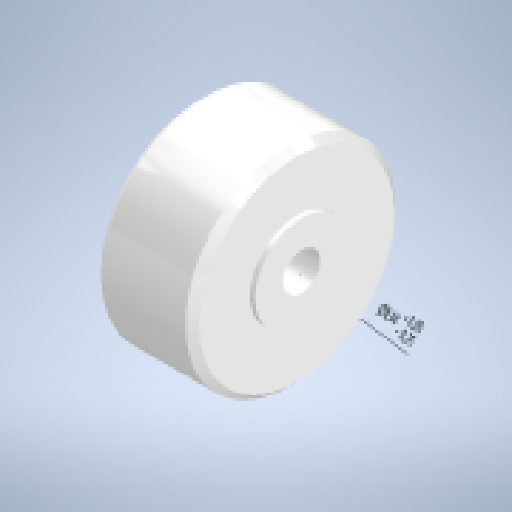
# Autodesk Inventor part: Wiel
Saved by Autodesk Inventor 2023.2 (Build 272271000, 271)
## iProperties
Created: 2023-06-25
Part Number: Wiel
Material: PAEK Plastic
Document SubType Name: Modeling
Designer: Jeroen
Density: 1.32 g/cm^3
Appearance: Smooth - White
Author: Jeroen
Autodesk Inventor part; units mm, degrees
ref_plane "YZ Plane" through (0, 0, 0) normal (1, 0, 0) x (0, 1, 0)
ref_plane "XZ Plane" through (0, 0, 0) normal (0, 1, 0) x (-1, 0, 0)
ref_plane "XY Plane" through (0, 0, 0) normal (0, 0, 1) x (1, 0, 0)
sketch "Sketch1" plane through (0, 0, 0) normal (0, 0, 1) x (1, 0, 0)
  line L0 (17.838, -21.8164) -> (22.838, -21.8164) construction
  line L1 (17.838, -13.8408) -> (22.838, -13.8408) construction
  line L2 (22.838, -13.8408) -> (22.838, -21.8164) construction
  line L3 (47.838, -13.8408) -> (52.838, -13.8408) construction
  line L4 (47.838, -21.8164) -> (52.838, -21.8164) construction
  line L5 (47.838, -21.8164) -> (47.838, -13.8408) construction
  line L6 (46.838, -17.8286) -> (46.838, -7.8286)
  line L7 (46.838, -7.8286) -> (45.838, -7.8286)
  line L8 (45.838, -7.8286) -> (45.838, 3.1714)
  line L9 (45.838, 3.1714) -> (44.338, 4.6714)
  line L10 (44.338, 4.6714) -> (26.338, 4.6714)
  line L11 (26.338, 4.6714) -> (24.838, 3.1714)
  line L12 (24.838, 3.1714) -> (24.838, -7.8286)
  line L13 (24.838, -7.8286) -> (23.838, -7.8286)
  line L14 (23.838, -7.8286) -> (23.838, -17.8286)
  line L15 (35.338, 4.6714) -> (35.338, -17.8286) construction
  line L16 (22.838, -17.8286) -> (23.838, -17.8286) construction
  line L17 (46.838, -17.8286) -> (23.838, -17.8286)
  line L18 (46.838, -17.8286) -> (47.838, -17.8286) construction
  line L19 (23.838, -13.8286) -> (46.838, -13.8286)
  point P0 (0, 0)
  dimension "d2" = 23
  dimension "d3" = 21
  dimension "d4" = 1.5
  dimension "d5" = 1.5
  dimension "d6" = 22.5
  dimension "d7" = 10
  dimension "d9" = 8
  constraints: 40 end point, 5 horizontal, 4 equal length, 4 midpoint, 4 point on line, 3 perpendicular, 3 vertical, 2 parallel, 1 collinear, 8 other
  measures "d2" distance between parallel lines of L6 L14
  measures "d3" distance between parallel lines of L8 L12
  measures "d4" horizontal distance of L9.end L8.end
  measures "d5" horizontal distance of L9.end L8.end
  measures "d6" distance between parallel lines of L17 L10
  measures "d7" distance of L6.start L6.end
  measures "d9" diameter of L19 L17
revolve "Revolution1" add sketch "Sketch1" angle 360 about axis through (46.838, -17.8286, 0) along (-1, 0, 0) contours L19 L14 L13 L12 L11 L10 L9 L8 L7 L6
equation "\"d5\" = d4"
body "Solid1"
